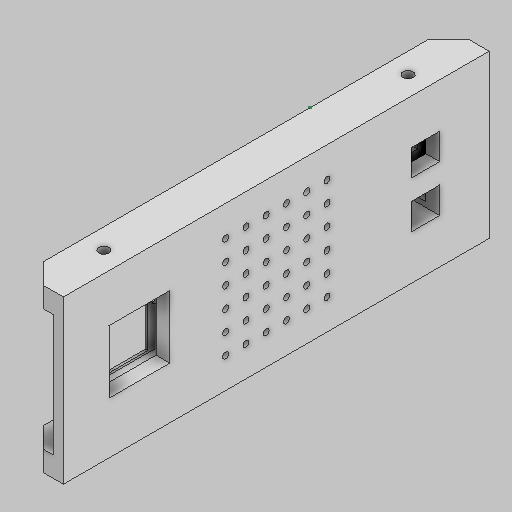
# Autodesk Inventor part: Puered_Puertos
Saved by Autodesk Inventor 2027 (Build 310192000, 192)
## iProperties
Created: 2026-11-23
Part Number: Puered_Puertos
Material: Genérico
Document SubType Name: Modeling
Designer: Alexander
Density: 1 g/cm^3
Appearance: Valor por defecto
Author: Alexander
Autodesk Inventor part; units mm, degrees
ref_plane "YZ Plane" through (0, 0, 0) normal (1, 0, 0) x (0, 1, 0)
ref_plane "XZ Plane" through (0, 0, 0) normal (0, 1, 0) x (-1, 0, 0)
ref_plane "XY Plane" through (0, 0, 0) normal (0, 0, 1) x (1, 0, 0)
sketch "Boceto1" plane through (0, 0, 0) normal (1, 0, 0) x (0, 1, 0)
  line L0 (0, 141.4615) -> (-80, 141.4615)
  line L1 (-80, 141.4615) -> (-80, -68.5385)
  line L2 (-80, -68.5385) -> (0, -68.5385)
  line L3 (0, -68.5385) -> (0, 141.4615)
  point P0 (0, 0)
  dimension "d0" = 80
  dimension "d1" = 210
  constraints: 8 end point, 2 parallel, 1 horizontal, 1 perpendicular
  measures "d0" distance of L2.end L1.end
  measures "d1" distance of L1.end L0.end
extrude "Extrusión1" add sketch "Boceto1" along normal blind 20
sketch "Boceto2" plane through (0, 0, 0) normal (-1, 0, 0) x (0, 0, 1)
  line L0 (-68.5385, 0) -> (141.4615, 0) projected
  line L1 (141.4615, 0) -> (141.4615, -80) projected
  line L2 (-68.5385, 0) -> (141.4615, 0)
  line L3 (141.4615, 0) -> (141.4615, -10)
  line L4 (141.4615, -10) -> (-68.5385, -10)
  line L5 (-68.5385, -10) -> (-68.5385, 0)
  line L6 (-68.5385, -80) -> (141.4615, -80)
  line L7 (141.4615, -80) -> (141.4615, -70)
  line L8 (141.4615, -70) -> (-68.5385, -70)
  line L9 (-68.5385, -70) -> (-68.5385, -80)
  line L10 (-68.5385, -10) -> (141.4615, -10)
  line L11 (141.4615, -10) -> (141.4615, -70)
  line L12 (141.4615, -70) -> (-68.5385, -70)
  line L13 (-68.5385, -70) -> (-68.5385, -10)
  point P0 (0, 0)
  dimension "d4" = 10
  dimension "d5" = 10
  constraints: 24 end point, 6 parallel, 3 horizontal, 3 perpendicular, 3 point on line
  measures "d4" distance of L2.end L3.end
  measures "d5" distance of L7.end L6.end
extrude "Extrusión2" cut sketch "Boceto2" against normal blind 15 contours L4 L1 L8 L13
sketch "Boceto3" plane through (0, 0, 141.4615) normal (0, 1, 0) x (1, 0, 0)
  line L0 (0, 0) -> (0, 210) projected
  line L1 (0, 210) -> (0, 200)
  line L2 (0, 0) -> (0, 10)
  line L3 (20, 0) -> (20, 210) projected
  line L4 (20, 0) -> (10, 0)
  line L5 (0, 0) -> (20, 0) projected
  line L6 (10, 0) -> (0, 10)
  line L7 (0, 210) -> (20, 210) projected
  line L8 (20, 210) -> (10, 210)
  line L9 (10, 210) -> (0, 200)
  line L10 (0, 200) -> (0, 210)
  line L11 (0, 210) -> (10, 210)
  line L12 (0, 10) -> (0, 0)
  line L13 (10, 0) -> (0, 0)
  point P0 (0, 141.4615)
  dimension "d8" = 10
  dimension "d9" = 10
  dimension "d10" = 10
  dimension "d11" = 10
  constraints: 20 end point, 2 collinear, 2 midpoint, 2 perpendicular, 2 point on line
  measures "d8" distance of L0.end L1.end
  measures "d9" distance of L0.start L2.end
  measures "d10" distance of L3.start L4.end
  measures "d11" distance of L3.end L8.end
extrude "Extrusión3" cut sketch "Boceto3" against normal blind 126.75 contours L0 L6 L5 | L0 L7 L9
sketch "Boceto4" plane through (20, 0, 141.4615) normal (0, 1, 0) x (1, 0, 0)
  circle A0 centre (-10, 180) radius 2.5
  circle A1 centre (-10, 30) radius 2.5
  line L0 (-10, 0) -> (0, 0) projected
  line L1 (-10, 210) -> (0, 210) projected
  line L2 (0, 210) -> (0, 0) projected
  point P0 (-20, 141.4615)
  dimension "d14" = 5
  dimension "d15" = 5
  dimension "d16" = 30
  dimension "d17" = 30
  dimension "d18" = 10
  dimension "d19" = 10
  constraints: 2 centre point
  measures "d14" diameter of A0
  measures "d15" diameter of A1
  measures "d16" distance from line of L0 A1.centre
  measures "d17" distance from line of L1 A0.centre
  measures "d18" distance from line of A0.centre L2
  measures "d19" distance from line of A1.centre L2
extrude "Extrusión4" cut sketch "Boceto4" against normal blind 126.75
sketch "Boceto5" plane through (15, 0, 0) normal (-1, 0, 0) x (0, 0, 1)
  line L0 (-50.5385, -17) -> (-24.5385, -17)
  line L1 (-24.5385, -17) -> (-24.5385, -63)
  line L2 (-24.5385, -63) -> (-50.5385, -63)
  line L3 (-50.5385, -63) -> (-50.5385, -17)
  line L4 (-68.5385, -70) -> (-68.5385, -10) projected
  line L5 (-58.5385, 0) -> (131.4615, 0) projected
  line L6 (12.4615, -17) -> (60.4615, -17)
  line L7 (60.4615, -17) -> (60.4615, -65)
  line L8 (60.4615, -65) -> (12.4615, -65)
  line L9 (12.4615, -65) -> (12.4615, -17)
  line L10 (-68.5385, 0) -> (141.4615, 0) projected
  line L11 (-68.5385, 0) -> (141.4615, 0)
  line L12 (141.4615, 0) -> (141.4615, -80)
  line L13 (141.4615, -80) -> (-68.5385, -80)
  line L14 (-68.5385, -80) -> (-68.5385, 0)
  line L15 (85.4615, -21.5) -> (122.4615, -21.5)
  line L16 (122.4615, -21.5) -> (122.4615, -58.5)
  line L17 (122.4615, -58.5) -> (85.4615, -58.5)
  line L18 (85.4615, -58.5) -> (85.4615, -21.5)
  line L19 (-44.1592, -22) -> (-30.1592, -22)
  line L20 (-30.1592, -22) -> (-30.1592, -58)
  line L21 (-30.1592, -58) -> (-44.1592, -58)
  line L22 (-44.1592, -58) -> (-44.1592, -22)
  line L23 (-44.1592, -58) -> (-30.1592, -58)
  line L24 (-30.1592, -58) -> (-30.1592, -45)
  line L25 (-30.1592, -45) -> (-44.1592, -45)
  line L26 (-44.1592, -45) -> (-44.1592, -58)
  line L27 (-44.1592, -22) -> (-30.1592, -22)
  line L28 (-30.1592, -22) -> (-30.1592, -35)
  line L29 (-30.1592, -35) -> (-44.1592, -35)
  line L30 (-44.1592, -35) -> (-44.1592, -22)
  line L31 (-44.1592, -28.5) -> (-50.5385, -28.5)
  line L32 (-30.1592, -28.5) -> (-24.5385, -28.5)
  line L33 (-44.1592, -51.5) -> (-50.5385, -51.5)
  line L34 (-30.1592, -51.5) -> (-24.5385, -51.5)
  circle A0 centre (-47.3488, -28.5) radius 1.5
  circle A1 centre (-27.3488, -28.5) radius 1.5
  circle A2 centre (-47.3488, -51.5) radius 1.5
  circle A3 centre (-27.3488, -51.5) radius 1.5
  line L35 (88.9615, -24.5) -> (118.9615, -24.5)
  line L36 (118.9615, -24.5) -> (118.9615, -54.5)
  line L37 (118.9615, -54.5) -> (88.9615, -54.5)
  line L38 (88.9615, -54.5) -> (88.9615, -24.5)
  line L39 (15.4615, -20) -> (57.4615, -20)
  line L40 (57.4615, -20) -> (57.4615, -62)
  line L41 (57.4615, -62) -> (15.4615, -62)
  line L42 (15.4615, -62) -> (15.4615, -20)
  circle A4 centre (85.4615, -34.7) radius 1.5
  circle A5 centre (122.4615, -34.7) radius 1.5
  circle A6 centre (85.4615, -34.7) radius 2.5
  circle A7 centre (122.4615, -34.7) radius 2.5
  point P0 (0, 0)
  point P1 (-37.1592, -22)
  point P2 (85.4615, -37.2)
  point P3 (122.4615, -37.2)
  point P4 (122.4615, -32.2)
  point P5 (85.4615, -32.2)
  dimension "d22" = 18
  dimension "d23" = 26
  dimension "d24" = 46
  dimension "d25" = 17
  dimension "d26" = 48
  dimension "d27" = 48
  dimension "d28" = 81
  dimension "d29" = 37
  dimension "d30" = 37
  dimension "d31" = 19
  dimension "d32" = 21.5
  dimension "d33" = 14
  dimension "d35" = 5
  dimension "d36" = 5
  dimension "d37" = 13
  dimension "d38" = 13
  dimension "d39" = 3
  dimension "d40" = 3
  dimension "d41" = 3
  dimension "d42" = 3
  dimension "d43" = 30
  dimension "d44" = 30
  dimension "d45" = 3.5
  dimension "d46" = 3
  dimension "d47" = 42
  dimension "d48" = 42
  dimension "d49" = 3
  dimension "d50" = 3
  dimension "d51" = 37
  dimension "d52" = 3.5
  dimension "d53" = 10.2
  dimension "d54" = 3
  dimension "d55" = 3
  dimension "d56" = 5
  dimension "d57" = 5
  constraints: 80 end point, 18 parallel, 11 perpendicular, 9 horizontal, 9 midpoint, 8 centre point, 8 point on line, 4 coincident
  measures "d22" distance between parallel lines of L4 L3
  measures "d23" distance of L0.start L0.end
  measures "d24" distance of L0.end L1.end
  measures "d25" distance between parallel lines of L0 L5
  measures "d26" distance of L7.end L8.end
  measures "d27" distance of L6.end L7.end
  measures "d28" distance between parallel lines of L12 L7
  measures "d29" distance of L16.end L17.end
  measures "d30" distance of L15.end L16.end
  measures "d31" distance between parallel lines of L16 L12
  measures "d32" distance between parallel lines of L10 L15
  measures "d33" distance of L20.end L21.end
  measures "d35" distance from line of point (-37.159, -22) L0
  measures "d36" distance between parallel lines of L21 L2
  measures "d37" distance of L24.end L23.end
  measures "d38" distance of L27.end L28.end
  measures "d39" diameter of A0
  measures "d40" diameter of A1
  measures "d41" diameter of A2
  measures "d42" diameter of A3
  measures "d43" distance of L36.end L37.end
  measures "d44" distance of L35.end L36.end
  measures "d45" distance between parallel lines of L18 L38
  measures "d46" distance between parallel lines of L35 L15
  measures "d47" distance of L39.start L39.end
  measures "d48" distance of L41.end L39.start
  measures "d49" distance between parallel lines of L6 L39
  measures "d50" distance between parallel lines of L9 L42
  measures "d51" distance of point (85.461, -34.7) point (122.461, -34.7)
  measures "d52" distance from line of point (85.461, -34.7) L38
  measures "d53" distance from line of L35 point (85.461, -34.7)
  measures "d54" diameter of A4
  measures "d55" diameter of A5
  measures "d56" diameter of A6
  measures "d57" diameter of A7
extrude "Extrusión5" add sketch "Boceto5" along normal blind 7 contours L15 L16 A7 L17 L18 A6 | A6 L18 A4 | L18 A4 A6 | A7 L16 A5 | L16 A5 A7
extrude "Extrusión6" add sketch "Boceto5" along normal blind 7.8 contours L0 L1 L32 A1 L20 L19 L22 L31 A0 L3 | L31 A0 L22 L33 A2 L3 | L1 L34 A3 L20 L32 A1 | L33 A2 L22 L21 L20 L34 A3 L1 L2 L3 | L29 L20 L25 L22
extrude "Extrusión7" add sketch "Boceto5" along normal blind 10 contours L6 L7 L8 L9
extrude "Extrusión8" cut sketch "Boceto5" against normal blind 10 contours L22 L19 L20 L29 | L22 L25 L20 L21 | L35 L36 L37 L38
sketch "Boceto6" plane through (15, -63, -50.5385) normal (0, 0, -1) x (-1, 0, 0)
  line L0 (7.8, 41) -> (-5, 41) projected
  line L1 (0, 4.5) -> (7, 4.5) projected
  line L2 (5.8, 41) -> (1.8, 41)
  line L3 (1.8, 41) -> (1.8, 4.5)
  line L4 (1.8, 4.5) -> (5.8, 4.5)
  line L5 (5.8, 4.5) -> (5.8, 41)
  line L6 (7.8, 46) -> (7.8, 0) projected
  line L7 (1.8, 41) -> (5.8, 41)
  line L8 (5.8, 41) -> (5.8, 38)
  line L9 (5.8, 38) -> (1.8, 38)
  line L10 (1.8, 38) -> (1.8, 41)
  line L11 (1.8, 4.5) -> (5.8, 4.5)
  line L12 (5.8, 4.5) -> (5.8, 7.5)
  line L13 (5.8, 7.5) -> (1.8, 7.5)
  line L14 (1.8, 7.5) -> (1.8, 4.5)
  line L15 (5.8, 7.5) -> (1.8, 7.5)
  line L16 (1.8, 7.5) -> (1.8, 38)
  line L17 (1.8, 38) -> (5.8, 38)
  line L18 (5.8, 38) -> (5.8, 7.5)
  point P0 (15, 63)
  point P1 (1.8, 7.5)
  dimension "d66" = 4
  dimension "d67" = 2
  dimension "d68" = 3
  dimension "d69" = 3
  constraints: 32 end point, 8 parallel, 4 horizontal, 4 perpendicular, 4 point on line
  measures "d66" distance of L4.end L3.end
  measures "d67" distance between parallel lines of L5 L6
  measures "d68" distance of L7.end L8.end
  measures "d69" distance of L12.end L11.end
extrude "Extrusión9" cut sketch "Boceto6" against normal blind 216.25 contours L5 L13 L3 L9
sketch "Boceto7" plane through (20, 0, 0) normal (1, 0, 0) x (0, 0, -1)
  line L0 (-141.4615, -80) -> (68.5385, -80) projected
  line L1 (68.5385, -80) -> (-141.4615, -80)
  line L2 (-131.4615, -80) -> (58.5385, -80) projected
  line L3 (-76.4615, 0) -> (-36.4615, 0)
  line L4 (-76.4615, 0) -> (3.5385, 0)
  line L5 (3.5385, -80) -> (-76.4615, -80)
  circle A0 centre (-71.4615, -5) radius 1.5
  line L6 (-71.4615, -5) -> (-68.1788, -5)
  line L7 (-71.4615, -5) -> (-71.4615, -7.9632)
  circle A1 centre (-61.4615, -5) radius 1.5
  circle A2 centre (-51.4615, -5) radius 1.5
  circle A3 centre (-41.4615, -5) radius 1.5
  circle A4 centre (-31.4615, -5) radius 1.5
  circle A5 centre (-21.4615, -5) radius 1.5
  circle A6 centre (-11.4615, -5) radius 1.5
  circle A7 centre (-1.4615, -5) radius 1.5
  circle A8 centre (-71.4615, -15) radius 1.5
  circle A9 centre (-61.4615, -15) radius 1.5
  circle A10 centre (-51.4615, -15) radius 1.5
  circle A11 centre (-41.4615, -15) radius 1.5
  circle A12 centre (-31.4615, -15) radius 1.5
  circle A13 centre (-21.4615, -15) radius 1.5
  circle A14 centre (-11.4615, -15) radius 1.5
  circle A15 centre (-1.4615, -15) radius 1.5
  circle A16 centre (-71.4615, -25) radius 1.5
  circle A17 centre (-61.4615, -25) radius 1.5
  circle A18 centre (-51.4615, -25) radius 1.5
  circle A19 centre (-41.4615, -25) radius 1.5
  circle A20 centre (-31.4615, -25) radius 1.5
  circle A21 centre (-21.4615, -25) radius 1.5
  circle A22 centre (-11.4615, -25) radius 1.5
  circle A23 centre (-1.4615, -25) radius 1.5
  circle A24 centre (-71.4615, -35) radius 1.5
  circle A25 centre (-61.4615, -35) radius 1.5
  circle A26 centre (-51.4615, -35) radius 1.5
  circle A27 centre (-41.4615, -35) radius 1.5
  circle A28 centre (-31.4615, -35) radius 1.5
  circle A29 centre (-21.4615, -35) radius 1.5
  circle A30 centre (-11.4615, -35) radius 1.5
  circle A31 centre (-1.4615, -35) radius 1.5
  circle A32 centre (-71.4615, -45) radius 1.5
  circle A33 centre (-61.4615, -45) radius 1.5
  circle A34 centre (-51.4615, -45) radius 1.5
  circle A35 centre (-41.4615, -45) radius 1.5
  circle A36 centre (-31.4615, -45) radius 1.5
  circle A37 centre (-21.4615, -45) radius 1.5
  circle A38 centre (-11.4615, -45) radius 1.5
  circle A39 centre (-1.4615, -45) radius 1.5
  circle A40 centre (-71.4615, -55) radius 1.5
  circle A41 centre (-61.4615, -55) radius 1.5
  circle A42 centre (-51.4615, -55) radius 1.5
  circle A43 centre (-41.4615, -55) radius 1.5
  circle A44 centre (-31.4615, -55) radius 1.5
  circle A45 centre (-21.4615, -55) radius 1.5
  circle A46 centre (-11.4615, -55) radius 1.5
  circle A47 centre (-1.4615, -55) radius 1.5
  circle A48 centre (-71.4615, -65) radius 1.5
  circle A49 centre (-61.4615, -65) radius 1.5
  circle A50 centre (-51.4615, -65) radius 1.5
  circle A51 centre (-41.4615, -65) radius 1.5
  circle A52 centre (-31.4615, -65) radius 1.5
  circle A53 centre (-21.4615, -65) radius 1.5
  circle A54 centre (-11.4615, -65) radius 1.5
  circle A55 centre (-1.4615, -65) radius 1.5
  circle A56 centre (-71.4615, -75) radius 1.5
  circle A57 centre (-61.4615, -75) radius 1.5
  circle A58 centre (-51.4615, -75) radius 1.5
  circle A59 centre (-41.4615, -75) radius 1.5
  circle A60 centre (-31.4615, -75) radius 1.5
  circle A61 centre (-21.4615, -75) radius 1.5
  circle A62 centre (-11.4615, -75) radius 1.5
  circle A63 centre (-1.4615, -75) radius 1.5
  point P0 (0, 0)
  point P1 (-141.4615, 0)
  dimension "d72" = 40
  dimension "d74" = 80
  dimension "d75" = 3
  dimension "d80" = 10
  dimension "d83" = 10
  constraints: 64 centre point, 12 end point, 3 horizontal, 2 vertical, 1 parallel, 1 point on line, 126 other
  measures "d72" distance of L3.start L3.end
  measures "d74" distance of L5.start L5.end
  measures "d75" diameter of A0
  measures "d80" distance of L6.start A1.centre
  measures "d83" distance of L6.start A8.centre
extrude "Extrusión10" cut sketch "Boceto7" against normal blind 5 contours A9 | A10 | A11 | A12 | A13 | A14 | A17 | A18 | A19 | A20 | A21 | A22 | A25 | A26 | A27 | A28 | A29 | A30 | A33 | A34 | A35 | A36 | A37 | A38 | A41 | A42 | A43 | A44 | A45 | A46 | A49 | A50 | A51 | A52 | A53 | A54
sketch "Boceto8" plane through (20, 0, 141.4615) normal (0, 1, 0) x (1, 0, 0)
  point P0 (-20, 141.4615)
sketch "Boceto9" plane through (8, 0, 0) normal (-1, 0, 0) x (0, 0, 1)
  line L0 (118.9615, -24.5) -> (88.9615, -24.5) projected
  line L1 (88.9615, -24.5) -> (118.9615, -24.5)
  line L2 (118.9615, -24.5) -> (118.9615, -23.5)
  line L3 (118.9615, -23.5) -> (88.9615, -23.5)
  line L4 (88.9615, -23.5) -> (88.9615, -24.5)
  point P0 (0, 0)
  dimension "d88" = 1
  constraints: 8 end point, 2 parallel, 1 horizontal, 1 perpendicular
  measures "d88" distance of L2.end L1.end
extrude "Extrusión11" cut sketch "Boceto9" against normal blind 19
